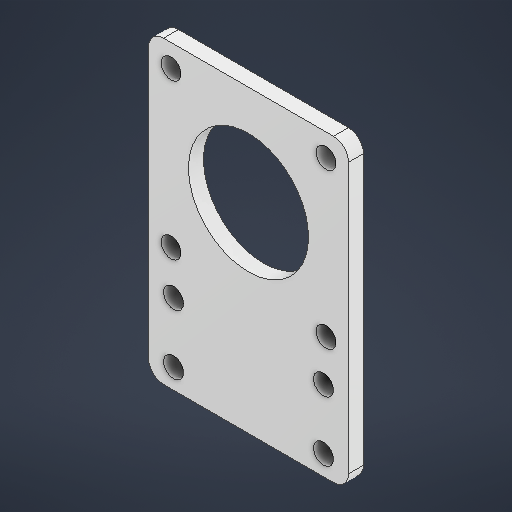
# Autodesk Inventor part: D
Saved by Autodesk Inventor 2026.2 (Build 302298010, 298A)
## iProperties
Created: 2026-03-19
Part Number: D
Material: PC/ABS 플라스틱
Document SubType Name: Modeling
Designer: work
Density: 1.1 g/cm^3
Appearance: 매끄러움 - 흰색
Mass: 6.06987 g
Surface Area: 47.9104 cm^2
Volume: 5.51806 cm^3
Author: work
Autodesk Inventor part; units mm, degrees
ref_plane "YZ Plane" through (0, 0, 0) normal (1, 0, 0) x (0, 1, 0)
ref_plane "XZ Plane" through (0, 0, 0) normal (0, 1, 0) x (-1, 0, 0)
ref_plane "XY Plane" through (0, 0, 0) normal (0, 0, 1) x (1, 0, 0)
sketch "스케치1" plane through (0, 0, 0) normal (0, 0, 1) x (1, 0, 0)
  line L0 (-15.5, -15.5) -> (15.5, -15.5) construction
  line L1 (15.5, -15.5) -> (15.5, 15.5) construction
  line L2 (15.5, 15.5) -> (-15.5, 15.5) construction
  line L3 (-15.5, 15.5) -> (-15.5, -15.5) construction
  line L4 (-15.5, -15.5) -> (15.5, 15.5) construction
  line L5 (15.5, -15.5) -> (-15.5, 15.5) construction
  circle A0 centre (-15.5, 15.5) radius 2
  circle A1 centre (15.5, 15.5) radius 2
  circle A2 centre (-15.5, -15.5) radius 2
  circle A3 centre (15.5, -15.5) radius 2
  circle A4 centre (0, 0) radius 12
  line L6 (-20, -20) -> (20, -20) construction
  line L7 (20, -20) -> (20, 20)
  line L8 (20, 20) -> (-20, 20)
  line L9 (-20, 20) -> (-20, -20)
  line L10 (-20, -20) -> (20, 20) construction
  line L11 (20, -20) -> (-20, 20) construction
  line L12 (-20, -20) -> (20, -20) construction
  line L13 (20, -20) -> (20, -40)
  line L14 (20, -40) -> (-20, -40)
  line L15 (-20, -40) -> (-20, -20)
  line L16 (0, -20) -> (0, -40) construction
  line L17 (-15, -36) -> (15, -36) construction
  line L18 (15, -36) -> (15, -24) construction
  line L19 (15, -24) -> (-15, -24) construction
  line L20 (-15, -24) -> (-15, -36) construction
  line L21 (-15, -36) -> (15, -24) construction
  line L22 (15, -36) -> (-15, -24) construction
  circle A5 centre (-15, -24) radius 2
  circle A6 centre (-15, -36) radius 2
  circle A7 centre (15, -24) radius 2
  circle A8 centre (15, -36) radius 2
  point P0 (0, -30)
  dimension "d0" = 31
  dimension "d1" = 31
  dimension "d2" = 4
  dimension "d3" = 4
  dimension "d4" = 4
  dimension "d5" = 4
  dimension "d6" = 24
  dimension "d7" = 40
  dimension "d8" = 40
  dimension "d9" = 20
  dimension "d10" = 30
  dimension "d11" = 12
  dimension "d12" = 4
  dimension "d13" = 4
  dimension "d14" = 4
  dimension "d15" = 4
  constraints: 46 end point, 9 centre point, 9 coincident, 9 midpoint, 8 parallel, 4 horizontal, 4 perpendicular
  measures "d0" distance of L2.end L1.end
  measures "d1" distance of L0.end L1.end
  measures "d2" diameter of A0
  measures "d3" diameter of A1
  measures "d4" diameter of A2
  measures "d5" diameter of A3
  measures "d6" diameter of A4
  measures "d7" distance of L8.end L7.end
  measures "d8" distance of L7.end L6.end
  measures "d9" distance of L6.end L13.end
  measures "d10" distance of L19.end L18.end
  measures "d11" distance of L18.end L17.end
  measures "d12" diameter of A5
  measures "d13" diameter of A6
  measures "d14" diameter of A7
  measures "d15" diameter of A8
extrude "돌출1" add sketch "스케치1" along normal blind 3
fillet "모깎기1" radius 3 4 edges at (20, 20, 1.5) (-20, 20, 1.5) (20, -40, 1.5) (-20, -40, 1.5)
